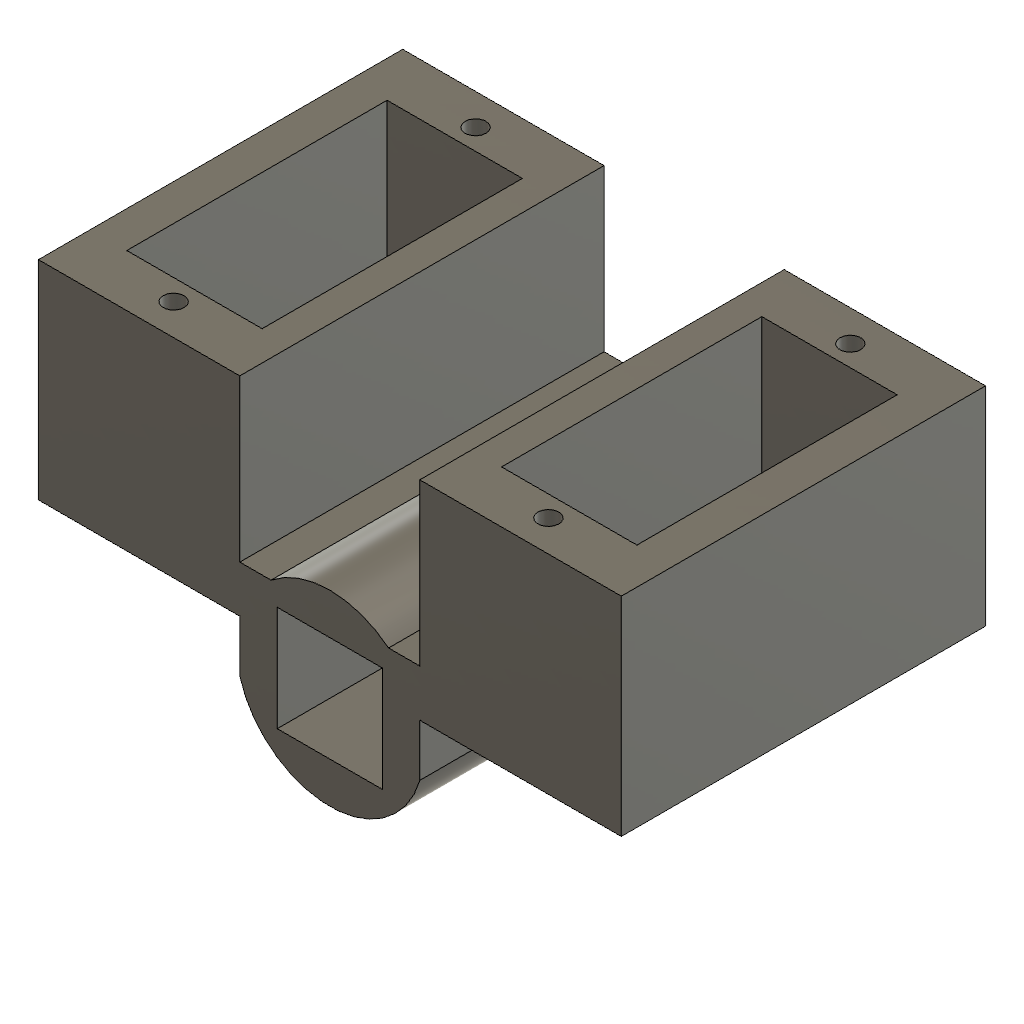
rc-airplanes-trainer-airplane-fusion-parts-servo (Autodesk Fusion 360 design; units mm, degrees)
Autodesk Fusion 360 part; units mm, degrees
sketch "Sketch1" plane through (0, 0, 0) normal (0, 1, 0) x (1, 0, 0)
  line L0 (6.5, -12.5) -> (-6.5, -12.5)
  line L1 (-6.5, -12.5) -> (-6.5, 12.5)
  line L2 (-6.5, 12.5) -> (6.5, 12.5)
  line L3 (6.5, 12.5) -> (6.5, -12.5)
  line L4 (6.5, -12.5) -> (-6.5, 12.5) construction
  line L5 (-6.5, -12.5) -> (6.5, 12.5) construction
  line L6 (10, -17.5) -> (-10, -17.5)
  line L7 (-10, -17.5) -> (-10, 17.5)
  line L8 (-10, 17.5) -> (10, 17.5)
  line L9 (10, 17.5) -> (10, -17.5)
  line L10 (10, -17.5) -> (-10, 17.5) construction
  line L11 (-10, -17.5) -> (10, 17.5) construction
  circle A0 centre (0, 14.5) radius 1
  circle A1 centre (0, -14.5) radius 1
  line L12 (-26, 17.5) -> (-26, -17.5)
  line L13 (-42.5, -12.5) -> (-42.5, 12.5)
  line L14 (-46, -17.5) -> (-46, 17.5)
  line L15 (-26, -17.5) -> (-46, -17.5)
  line L16 (-46, 17.5) -> (-26, 17.5)
  line L17 (-46, -17.5) -> (-26, 17.5) construction
  line L18 (-29.5, 12.5) -> (-29.5, -12.5)
  circle A2 centre (-36, 14.5) radius 1
  line L19 (-29.5, -12.5) -> (-42.5, -12.5)
  circle A3 centre (-36, -14.5) radius 1
  line L20 (-42.5, -12.5) -> (-29.5, 12.5) construction
  line L21 (-42.5, 12.5) -> (-29.5, 12.5)
  line L22 (-29.5, -12.5) -> (-42.5, 12.5) construction
  line L23 (-26, -17.5) -> (-46, 17.5) construction
  point P0 (-36, 0)
  point P1 (-36, 0)
  point P2 (-36, 0)
  dimension "d1" = 13
  dimension "d2" = 25
  dimension "d3" = 20
  dimension "d4" = 35
  dimension "d5" = 14.5
  dimension "d6" = 14.5
  dimension "d7" = 2
  dimension "d8" = 2
  dimension "d38" = 13
  dimension "d39" = 25
  dimension "d40" = 20
  dimension "d41" = 35
  dimension "d42" = 14.5
  dimension "d43" = 14.5
  dimension "d44" = 2
  dimension "d45" = 2
  constraint horizontal L0
  constraint perpendicular L0 L1
  constraint parallel L0 L2
  constraint parallel L1 L3
  constraint coincident L4 origin
  constraint coincident L5 origin
  constraint horizontal L6
  constraint perpendicular L6 L7
  constraint parallel L6 L8
  constraint parallel L7 L9
  constraint coincident L10 origin
  constraint coincident L11 origin
  constraint horizontal L19
  constraint perpendicular L13 L19
  constraint parallel L19 L21
  constraint parallel L13 L18
  constraint coincident P2 L22
  constraint coincident P2 L20
  constraint coincident P2 P1
  constraint horizontal L15
  constraint perpendicular L14 L15
  constraint parallel L15 L16
  constraint parallel L12 L14
  constraint coincident P2 L23
  constraint coincident P2 L17
  measures "d1" distance of L1.end L2.end
  measures "d2" distance of L0.end L1.end
  measures "d3" distance of L7.end L8.end
  measures "d4" distance of L6.end L7.end
  measures "d5" distance of origin A0.centre
  measures "d6" distance of origin A1.centre
  measures "d7" diameter of A0
  measures "d8" diameter of A1
  measures "d38" distance of L13.end L18.start
  measures "d39" distance of L13.end L13.start
  measures "d40" distance of L14.end L12.start
  measures "d41" distance of L14.start L14.end
  measures "d42" distance of A2.centre P2
  measures "d43" distance of P2 A3.centre
  measures "d44" diameter of A2
  measures "d45" diameter of A3
extrude "Extrude2" add sketch "Sketch1" along normal blind 5 contours L6 L7 L8 L9
sketch "Sketch2" plane through (0, 0, 0) normal (0, 0, 1) x (1, 0, 0)
  line L0 (0, 0) -> (-15, 0)
  line L1 (-10, 0) -> (-18, 0)
  line L2 (-18, 0) -> (-18, 2.5)
  circle A0 centre (-18, 2.5) radius 6.6
  circle A1 centre (-18, 2.5) radius 9
  dimension "d13" = 15
  dimension "d15" = 8
  dimension "d16" = 2.5
  dimension "d17" = 13.2
  dimension "d18" = 18
  constraint horizontal L0
  constraint coincident L0.start origin
  constraint coincident L0 L1.start
  constraint parallel L0 L1
  constraint perpendicular L1 L2
  constraint coincident L2.end A0.centre
  constraint concentric A0 A1
  measures "d13" distance of L0.start L0.end
  measures "d15" distance of L1.start L1.end
  measures "d16" distance of L1.end L2.end
  measures "d17" diameter of A0
  measures "d18" diameter of A1
extrude "Extrude3" add sketch "Sketch2" along normal up to surface (17.5 mm away)
extrude "Extrude4" add 1 faces at (-10.4667, 2.5, 0) along direction (0, 0, -1) up to surface (17.5 mm away)
sketch "Sketch3" plane through (0, 0, 17.5) normal (0, 0, 1) x (1, 0, 0)
  circle A0 centre (-18, 2.5) radius 6.6
  line L0 (-9.3542, 0) -> (10, 0)
  line L1 (10, 0) -> (10, 5)
  line L2 (10, 5) -> (-9.3542, 5)
  arc A1 (-9.3542, 5) -> (-9.3542, 0) centre (-18, 2.5) ccw
  line L3 (-18, 9.1) -> (-18, -6.5)
  line L4 (-20, -7.6621) -> (-20, -3.7897)
  line L5 (-16, -7.6621) -> (-16, -3.7897)
  line L6 (-20, -6.275) -> (-20, -16.275)
  line L7 (-16, -6.275) -> (-16, -16.275)
  line L8 (-16, -16.275) -> (-11, -16.275)
  line L9 (-20, -16.275) -> (-25, -16.275)
  line L10 (-25, -16.275) -> (-25, -3.1569)
  line L11 (-11, -16.275) -> (-11, -3.1569)
  dimension "d27" = 10
  dimension "d28" = 10
  dimension "d29" = 5
  dimension "d30" = 5
  constraint coincident A0 L3.start
  constraint vertical L3
  constraint coincident A0 L4.end
  constraint coincident A0 L5.end
  constraint coincident A1 L6.start
  constraint coincident L4 L6.start
  constraint parallel L4 L6
  constraint coincident A1 L7.start
  constraint coincident L5 L7.start
  constraint perpendicular L7 L8
  constraint perpendicular L6 L9
  constraint perpendicular L9 L10
  constraint coincident A1 L10.end
  constraint perpendicular L8 L11
  constraint coincident A1 L11.end
  constraint coincident A1 L3.end
  measures "d27" distance of L6.start L6.end
  measures "d28" distance of L7.start L7.end
  measures "d29" distance of L7.end L8.end
  measures "d30" distance of L6.end L9.end
extrude "Extrude5" cut sketch "Sketch3" against normal blind 58 contours A0 A1 L3 L5 | A0 A1 L3 L4
extrude "Extrude6" add sketch "Sketch3" against normal up to surface (35 mm away) contours A1 L5 L7 L8 L11 | A1 L4 L6 L9 L10
sketch "Sketch4" plane through (-25, 0, 0) normal (-1, 0, 0) x (0, 0, 1)
  line L0 (-17.5, -3.1569) -> (-17.5, -16.275)
  line L1 (-17.5, -16.275) -> (17.5, -16.275)
  line L2 (17.5, -16.275) -> (17.5, -3.1569)
  line L3 (17.5, -3.1569) -> (-17.5, -3.1569)
  circle A0 centre (8.5, -9.7159) radius 1.5
  circle A1 centre (-8.75, -9.7159) radius 1.5
  dimension "d34" = 3
  dimension "d35" = 3
  measures "d34" diameter of A0
  measures "d35" diameter of A1
extrude "Extrude7" cut sketch "Sketch4" against normal up to surface (14 mm away) contours A0 | A1
extrude "Extrude8" add sketch "Sketch1" along normal up to surface (5 mm away) contours L12 L14 L15 L16
sketch "Sketch5" plane through (0, 0, 17.5) normal (0, 0, 1) x (1, 0, 0)
  arc A0 (-26.6458, 0) -> (-25, -3.1569) centre (-18, 2.5) ccw
  line L0 (-25, -3.1569) -> (-25, -16.275)
  line L1 (-25, -16.275) -> (-20, -16.275)
  line L2 (-20, -16.275) -> (-20, -3.7897)
  arc A1 (-16, -3.7897) -> (-20, -3.7897) centre (-18, 2.5) ccw
  line L3 (-16, -3.7897) -> (-16, -16.275)
  line L4 (-16, -16.275) -> (-11, -16.275)
  line L5 (-11, -16.275) -> (-11, -3.1569)
  arc A2 (-11, -3.1569) -> (-9.3542, 0) centre (-18, 2.5) ccw
  line L6 (-9.3542, 0) -> (10, 0)
  line L7 (10, 0) -> (10, 5)
  line L8 (10, 5) -> (-9.3542, 5)
  arc A3 (-9.3542, 5) -> (-26.6458, 5) centre (-18, 2.5) ccw
  line L9 (-26.6458, 5) -> (-46, 5)
  line L10 (-46, 5) -> (-46, 0)
  line L11 (-46, 0) -> (-26.6458, 0)
  circle A4 centre (-18, 2.5) radius 9
  dimension "d48" = 18
  constraint concentric A0 A4
  measures "d48" diameter of A4
extrude "Extrude9" cut sketch "Sketch5" against normal blind 100 contours L0 L1 L2 A4 | L3 L4 L5 A4
extrude "Extrude10" add sketch "Sketch2" along normal up to surface (17.5 mm away)
extrude "Extrude11" add sketch "Sketch2" against normal up to surface (17.5 mm away)
ref_plane "WorkPlane1" through (-36.3229, 17, 0) normal (0, 1, 0) x (0, 0, 1)
sketch "Sketch6" plane through (0, 17, 0) normal (0, 1, 0) x (1, 0, 0)
  circle A0 centre (-18, 0) radius 1.75
  line L0 (-18, 0) -> (-18, -12)
  line L1 (-18, 0) -> (-18, 12)
  circle A1 centre (-18, -12) radius 1.5
  circle A2 centre (-18, 12) radius 1.5
  circle A3 centre (-18, 0) radius 4
  dimension "d56" = 3.5
  dimension "d62" = 12
  dimension "d63" = 12
  dimension "d64" = 3
  dimension "d65" = 3
  dimension "d86" = 8
  constraint coincident A0.centre L0.start
  constraint vertical L0
  constraint parallel L0 L1
  constraint coincident L0.end A1.centre
  constraint coincident L1.end A2.centre
  constraint concentric A0 A3
  measures "d56" diameter of A0
  measures "d62" distance of A0.centre L0.end
  measures "d63" distance of A0.centre L1.end
  measures "d64" diameter of A1
  measures "d65" diameter of A2
  measures "d86" diameter of A3
extrude "Extrude12" cut sketch "Sketch6" against normal blind 33 contours A0 L0 L1 | A0 L0 L1
sketch "Sketch7" plane through (0, 0, 17.5) normal (0, 0, 1) x (1, 0, 0)
  arc A0 (-26.6458, 0) -> (-9.3542, 0) centre (-18, 2.5) ccw
  line L0 (-9.3542, 0) -> (10, 0)
  line L1 (10, 0) -> (10, 5)
  line L2 (10, 5) -> (-9.3542, 5)
  arc A1 (-9.3542, 5) -> (-26.6458, 5) centre (-18, 2.5) ccw
  line L3 (-26.6458, 5) -> (-46, 5)
  line L4 (-46, 5) -> (-46, 0)
  line L5 (-46, 0) -> (-26.6458, 0)
  circle A2 centre (-18, 2.5) radius 6.6
  circle A3 centre (-18, 2.5) radius 6.25
  dimension "d59" = 12.5
  constraint concentric A0 A3
  measures "d59" diameter of A3
extrude "Extrude13" add sketch "Sketch7" against normal up to surface (35 mm away) contours A2
extrude "Extrude14" cut sketch "Sketch6" against normal blind 34 contours A1 | A2
extrude "Extrude15" cut sketch "Sketch6" against normal blind 36 contours A0 L0 L1 | A0 L0 L1
sketch "Sketch8" plane through (0, 0, 17.5) normal (0, 0, 1) x (1, 0, 0)
  circle A0 centre (-18, 2.5) radius 6.25
  arc A1 (-26.6458, 0) -> (-9.3542, 0) centre (-18, 2.5) ccw
  line L0 (-9.3542, 0) -> (10, 0)
  line L1 (10, 0) -> (10, 5)
  line L2 (10, 5) -> (-9.3542, 5)
  arc A2 (-9.3542, 5) -> (-26.6458, 5) centre (-18, 2.5) ccw
  line L3 (-26.6458, 5) -> (-46, 5)
  line L4 (-46, 5) -> (-46, 0)
  line L5 (-46, 0) -> (-26.6458, 0)
  circle A3 centre (-18, 2.5) radius 6.25
  line L6 (-12.95, 7.55) -> (-23.05, 7.55)
  line L7 (-23.05, 7.55) -> (-23.05, -2.55)
  line L8 (-23.05, -2.55) -> (-12.95, -2.55)
  line L9 (-12.95, -2.55) -> (-12.95, 7.55)
  line L10 (-12.95, 7.55) -> (-23.05, -2.55) construction
  line L11 (-23.05, 7.55) -> (-12.95, -2.55) construction
  point P0 (-18, 2.5)
  dimension "d70" = 10.1
  dimension "d71" = 10.1
  constraint concentric A0 A3
  constraint horizontal L6
  constraint perpendicular L6 L7
  constraint parallel L6 L8
  constraint parallel L7 L9
  constraint coincident L10 P0
  constraint coincident L11 P0
  constraint coincident P0 A0.centre
  measures "d70" distance of L7.end L8.end
  measures "d71" distance of L6.end L7.end
extrude "Extrude16" add sketch "Sketch8" against normal up to surface (35 mm away) contours A0 A3 L9 | A0 A3 L6 | A0 A3 L8 | A0 A3 L7
extrude "Extrude17" cut sketch "Sketch8" against normal up to surface (35 mm away) contours A0 A3 L6 L9 | A0 A3 L8 L9 | A0 A3 L6 L7 | A0 A3 L7 L8
extrude "Extrude18" add sketch "Sketch6" against normal blind 29 contours A0 L0 L1 | A0 L0 L1 | A1 | A2
extrude "Extrude19" cut sketch "Sketch8" against normal blind 45 contours A0 A3 L6 L7 L8 L9 | A0 A3 L6 L9 | A0 A3 L8 L9 | A0 A3 L6 L7 | A0 A3 L7 L8
sketch "Sketch9" plane through (0, 0, 17.5) normal (0, 0, 1) x (1, 0, 0)
  line L0 (-23.05, -2.55) -> (-23.05, 7.55)
  line L1 (-23.05, 7.55) -> (-12.95, 7.55)
  line L2 (-12.95, 7.55) -> (-12.95, -2.55)
  line L3 (-12.95, -2.55) -> (-23.05, -2.55)
  arc A0 (-26.6458, 0) -> (-9.3542, 0) centre (-18, 2.5) ccw
  line L4 (-9.3542, 0) -> (10, 0)
  line L5 (10, 0) -> (10, 5)
  line L6 (10, 5) -> (-9.3542, 5)
  arc A1 (-9.3542, 5) -> (-26.6458, 5) centre (-18, 2.5) ccw
  line L7 (-26.6458, 5) -> (-46, 5)
  line L8 (-46, 5) -> (-46, 0)
  line L9 (-46, 0) -> (-26.6458, 0)
  circle A2 centre (-18, 2.5) radius 9
  circle A3 centre (-18, 2.5) radius 16.3718
  line L10 (-34.1798, 5) -> (-26.6458, 5)
  line L11 (-9.3542, 5) -> (-1.8202, 5)
  line L12 (-9.3542, 0) -> (-1.8202, 0)
  line L13 (-26.6458, 0) -> (-34.1798, 0)
  constraint concentric A0 A2
  constraint concentric A2 A3
  constraint coincident L7 L10.start
  constraint coincident A3 L10.start
  constraint coincident A1.end L7.start
  constraint coincident L6.end A1.start
  constraint coincident L6 L11.end
  constraint coincident A3 L11.end
  constraint coincident A0.end L4.start
  constraint coincident A3 L12.end
  constraint coincident L4 L12.end
  constraint coincident A0.start L9.end
  constraint coincident L9 L13.end
  constraint coincident A3 L13.end
extrude "Extrude20" cut sketch "Sketch9" against normal blind 94 contours L6 A1 L7 A2 A3 L10 L11
extrude "Extrude21" cut sketch "Sketch9" against normal blind 144 contours A0 L4 L9 A2 A3 L12 L13
extrude "Extrude22" cut sketch "Sketch6" against normal blind 34 contours A0 L0 L1 | A0 L0 L1
extrude "Extrude23" cut sketch "Sketch6" against normal blind 7 contours A0 L0 L1 | A0 L0 L1 A3 | A0 L0 L1 | A0 L0 L1 A3
ref_plane "WorkPlane2" through (-18, -7.55, 0) normal (0, 1, 0) x (1, 0, 0)
sketch "Sketch10" plane through (0, -7.55, 0) normal (0, 1, 0) x (1, 0, 0)
  line L0 (-14.5097, 3.4932) -> (-21.5097, 3.4932)
  line L1 (-21.5097, 3.4932) -> (-21.5097, -3.5068)
  line L2 (-21.5097, -3.5068) -> (-14.5097, -3.5068)
  line L3 (-14.5097, -3.5068) -> (-14.5097, 3.4932)
  line L4 (-14.5097, 3.4932) -> (-21.5097, -3.5068) construction
  line L5 (-21.5097, 3.4932) -> (-14.5097, -3.5068) construction
  point P0 (-18.0097, -0.0068)
  dimension "d90" = 7
  dimension "d91" = 7
  constraint horizontal L0
  constraint perpendicular L0 L1
  constraint parallel L0 L2
  constraint parallel L1 L3
  constraint coincident L4 P0
  constraint coincident L5 P0
  measures "d90" distance of L1.end L2.end
  measures "d91" distance of L0.end L1.end
extrude "Extrude24" cut sketch "Sketch10" along normal blind 3
extrude "Extrude25" add 1 faces at (-18.01, -5.2, 3.5068) along direction (0, 0, -1) blind 0.5
extrude "Extrude26" add 1 faces at (-18.01, -5.2, -3.4932) along direction (0, 0, 1) blind 0.5
extrude "Extrude27" cut 1 faces at (-18.01, -5.2, -2.9932) along direction (0, 0, -1) blind 0.1
extrude "Extrude28" cut 1 faces at (-18.01, -5.2, 3.0068) along direction (0, 0, 1) blind 0.1
extrude "Extrude29" add 1 faces at (-18.01, -5.2, 3.1068) along direction (0, 0, -1) blind 0.5
extrude "Extrude30" add 1 faces at (-18.01, -5.2, -3.0932) along direction (0, 0, 1) blind 0.5
extrude "Extrude31" cut 1 faces at (-18.01, -5.2, -2.5932) along direction (0, 0, -1) blind 0.2
extrude "Extrude32" cut 1 faces at (-18.01, -5.2, 2.6068) along direction (0, 0, 1) blind 0.2
sketch "Sketch11" plane through (0, -4.55, 0) normal (0, -1, 0) x (1, 0, 0)
  line L0 (-14.5097, -2.7932) -> (-14.5097, 2.8068)
  line L1 (-14.5097, 2.8068) -> (-21.5097, 2.8068)
  line L2 (-21.5097, 2.8068) -> (-21.5097, -2.7932)
  line L3 (-21.5097, -2.7932) -> (-14.5097, -2.7932)
  circle A0 centre (-18, 0) radius 1.75
  line L4 (-16.3971, -2.7988) -> (-14.7747, -0.0112)
  line L5 (-14.7747, -0.0112) -> (-16.3776, 2.7876)
  line L6 (-16.3776, 2.7876) -> (-19.6029, 2.7988)
  line L7 (-19.6029, 2.7988) -> (-21.2253, 0.0112)
  line L8 (-21.2253, 0.0112) -> (-19.6224, -2.7876)
  line L9 (-19.6224, -2.7876) -> (-16.3971, -2.7988)
  point P0 (-18, 0)
  constraint coincident P0 A0.centre
extrude "Extrude36" add 2 faces at (-44.8333, 5, -4.1667) (8.8333, 5, -4.1667) along direction (0, 1, 0) blind 20
extrude "Extrude37" add 1 faces at (-26.6458, 18.3333, 5.8333) along direction (1, 0, 0) blind 3
extrude "Extrude38" add 1 faces at (-9.3542, 11.6667, -5.8333) along direction (-1, 0, 0) blind 3
extrude "Extrude39" cut 1 faces at (8.8333, 0, -4.1667) along direction (0, 1, 0) blind 5
extrude "Extrude40" cut 1 faces at (-44.8333, 0, -4.1667) along direction (0, 1, 0) blind 5
extrude "Extrude41" cut 1 faces at (-12.3542, 19.8363, 5.8333) along direction (1, 0, 0) blind 3
extrude "Extrude42" cut 1 faces at (-23.6458, 14.6726, 5.8333) along direction (-1, 0, 0) blind 3
extrude "Extrude33" [suppressed]
extrude "Extrude34" [suppressed]
extrude "Extrude35" [suppressed]
extrude "Extrude1" [suppressed]
